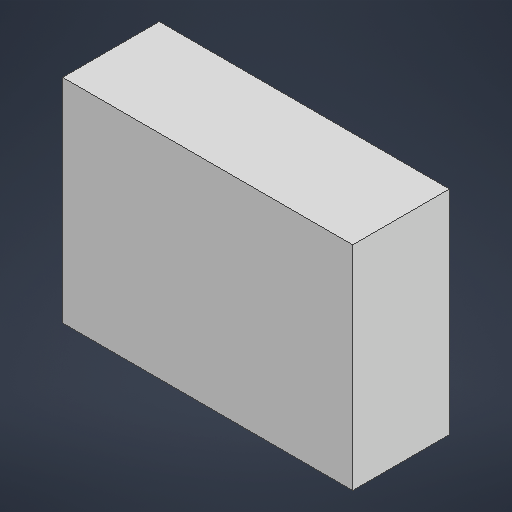
# Autodesk Inventor part: DUMMY-BUCK
Saved by Autodesk Inventor 2027.1 (Build 311270010, 270A)
## iProperties
Created: 2026-10-28
Part Number: DUMMY-BUCK
Material: Generic
Description: Buck converter
Document SubType Name: Modeling
Designer: shyan
Density: 1 g/cm^3
Appearance: Default
Mass: 15 g
Author: shyan
Autodesk Inventor part; units mm, degrees
ref_plane "YZ Plane" through (0, 0, 0) normal (1, 0, 0) x (0, 1, 0)
ref_plane "XZ Plane" through (0, 0, 0) normal (0, 1, 0) x (-1, 0, 0)
ref_plane "XY Plane" through (0, 0, 0) normal (0, 0, 1) x (1, 0, 0)
sketch "sk_body" plane through (0, 0, 0) normal (0, 0, 1) x (1, 0, 0)
  line L0 (-15, -11) -> (15, -11)
  line L1 (15, -11) -> (15, 11)
  line L2 (15, 11) -> (-15, 11)
  line L3 (-15, 11) -> (-15, -11)
  line L4 (-21, 0) -> (21, 0) construction
  line L5 (0, -15.4) -> (0, 15.4) construction
  point P0 (0, 0)
  dimension "d0" = 30
  dimension "d1" = 22
  constraints: 8 end point, 2 parallel, 1 horizontal, 1 perpendicular, 2 other
  measures "d0" distance of L0.start L0.end
  measures "d1" distance of L0.end L1.end
extrude "Body" add sketch "sk_body" along normal blind 10
equation "\"d0\" = bk_W"
equation "\"d1\" = bk_D"
equation "\"d2\" = bk_H"
equation "\"bk_W\" = 30"
equation "\"bk_D\" = 22"
equation "\"bk_H\" = 10"
body "Solid1"
